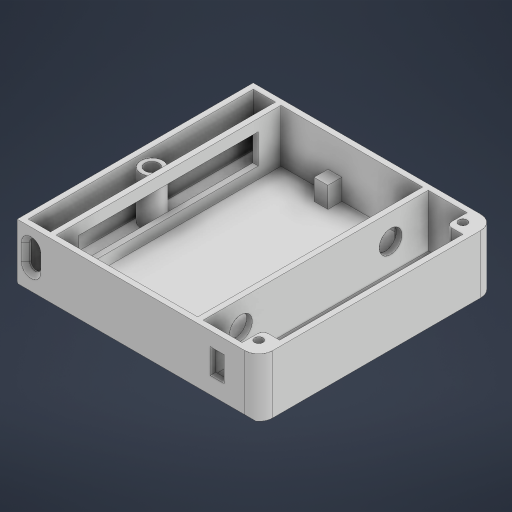
# Autodesk Inventor part: основа низ V2
Saved by Autodesk Inventor 2024 (Build 280153000, 153)
## iProperties
Created: 2026-05-29
Part Number: основа низ V2
Material: Типовые
Document SubType Name: Modeling
Designer: mitm
Density: 1 g/cm^3
Appearance: По умолчанию
Author: mitm
Autodesk Inventor part; units mm, degrees
ref_plane "YZ Plane" through (0, 0, 0) normal (1, 0, 0) x (0, 1, 0)
ref_plane "XZ Plane" through (0, 0, 0) normal (0, 1, 0) x (-1, 0, 0)
ref_plane "XY Plane" through (0, 0, 0) normal (0, 0, 1) x (1, 0, 0)
sketch "Эскиз1" plane through (0, 0, 0) normal (0, 1, 0) x (-1, 0, 0)
  line L0 (19.7795, 40.5) -> (-19.7795, 40.5)
  line L1 (-25.5, 34.7795) -> (-25.5, -34.7795)
  line L2 (-19.7795, -40.5) -> (19.7795, -40.5)
  line L3 (25.5, -34.7795) -> (25.5, 34.7795)
  line L4 (27.5, 42.5) -> (-27.5, 42.5)
  line L5 (-27.5, 42.5) -> (-27.5, -42.5)
  line L6 (-27.5, -42.5) -> (27.5, -42.5)
  line L7 (27.5, -42.5) -> (27.5, 42.5)
  line L8 (-27.5, 42.5) -> (-27.5, -42.5)
  line L9 (-27.5, -42.5) -> (-44.5, -42.5)
  line L10 (-49.5, -37.5) -> (-49.5, 37.5)
  line L11 (-44.5, 42.5) -> (-27.5, 42.5)
  line L12 (-27.5, 0) -> (-27.5, 33)
  line L13 (-27.5, 33) -> (-27.5, -33)
  line L14 (-47.5, -33) -> (-47.5, 33)
  line L15 (-27.5, 40.5) -> (-42.5, 40.5)
  line L16 (-47.5, 35.5) -> (-47.5, 33)
  line L17 (-27.5, -40.5) -> (-42.5, -40.5)
  line L18 (-47.5, -35.5) -> (-47.5, -33)
  circle A0 centre (-43.75, 36.75) radius 1.5
  circle A1 centre (-43.75, -36.75) radius 1.5
  arc A2 (-42.5, 40.5) -> (-47.5, 35.5) centre (-42.5, 35.5) ccw
  arc A3 (-44.5, 42.5) -> (-49.5, 37.5) centre (-44.5, 37.5) ccw
  arc A4 (-47.5, -35.5) -> (-42.5, -40.5) centre (-42.5, -35.5) ccw
  arc A5 (-49.5, -37.5) -> (-44.5, -42.5) centre (-44.5, -37.5) ccw
  line L19 (25.5, 40.5) -> (-25.5, 40.5)
  line L20 (-25.5, 40.5) -> (-25.5, -40.5)
  line L21 (-25.5, -40.5) -> (25.5, -40.5)
  line L22 (25.5, -40.5) -> (25.5, 40.5)
  line L23 (-27.5, 40.5) -> (-35, 40.5)
  line L24 (-27.5, 33) -> (-27.5, 40.5)
  line L25 (-47.5, 33) -> (-43.5, 33)
  line L26 (-37.5, 40.5) -> (-33.5, 40.5)
  line L27 (-37.5, 40.5) -> (-41.5, 40.5)
  line L28 (-41.5, 40.5) -> (-41.5, 35)
  arc A6 (-43.5, 33) -> (-41.5, 35) centre (-43.5, 35) ccw
  line L29 (-37.5, -40.5) -> (-33.5, -40.5)
  line L30 (-33.5, -40.5) -> (-41.5, -40.5)
  line L31 (-41.5, -40.5) -> (-41.5, -35)
  line L32 (-43.5, -33) -> (-47.5, -33)
  arc A7 (-41.5, -35) -> (-43.5, -33) centre (-43.5, -35) ccw
  line L33 (27.5, 42.5) -> (27.5, -42.5)
  line L34 (27.5, -42.5) -> (37.5, -42.5)
  line L35 (37.5, -42.5) -> (37.5, 42.5)
  line L36 (37.5, 42.5) -> (27.5, 42.5)
  line L37 (27.5, 40.5) -> (27.5, -40.5)
  line L38 (27.5, -40.5) -> (35.5, -40.5)
  line L39 (35.5, -40.5) -> (35.5, 40.5)
  line L40 (35.5, 40.5) -> (27.5, 40.5)
  line L41 (-25.5, -40.5) -> (-20.5, -40.5)
  line L42 (-20.5, -40.5) -> (-20.5, -35.5)
  line L43 (-20.5, -35.5) -> (-25.5, -35.5)
  line L44 (-25.5, -35.5) -> (-25.5, -40.5)
  line L45 (25.5, 40.5) -> (20.5, 40.5)
  line L46 (20.5, 40.5) -> (20.5, 35.5)
  line L47 (20.5, 35.5) -> (25.5, 35.5)
  line L48 (25.5, 35.5) -> (25.5, 40.5)
  line L49 (35.5, 40.5) -> (33.5, 40.5)
  line L50 (33.5, 40.5) -> (33.5, 20.5)
  line L51 (33.5, 20.5) -> (35.5, 20.5)
  line L52 (35.5, 20.5) -> (35.5, 40.5)
  line L53 (33.5, 40.5) -> (32.5, 40.5)
  line L54 (32.5, 40.5) -> (30.5, 40.5)
  line L55 (30.5, 40.5) -> (30.5, 20.5)
  line L56 (30.5, 20.5) -> (32.5, 20.5)
  line L57 (32.5, 20.5) -> (32.5, 40.5)
  line L58 (-3.7286, 40.5) -> (-8.7286, 40.5)
  line L59 (-8.7286, 40.5) -> (-8.7286, 35.5)
  line L60 (-8.7286, 35.5) -> (-3.7286, 35.5)
  line L61 (-3.7286, 35.5) -> (-3.7286, 40.5)
  line L62 (3.6011, -40.5) -> (8.6011, -40.5)
  line L63 (8.6011, -40.5) -> (8.6011, -35.5)
  line L64 (8.6011, -35.5) -> (3.6011, -35.5)
  line L65 (3.6011, -35.5) -> (3.6011, -40.5)
  point P0 (0, 0)
  point P1 (-49.5, -42.5)
  point P2 (-47.5, -40.5)
  point P3 (25.5, 37.3229)
  point P4 (22.3229, 40.5)
  point P5 (22.3229, -40.5)
  point P6 (25.5, -37.3229)
  point P7 (-41.5, -33)
  dimension "d112" = 5
  dimension "d113" = 5
  dimension "d114" = 5
  dimension "d115" = 5
  dimension "d116" = 2
  dimension "d117" = 20
  dimension "d118" = 1
  dimension "d119" = 2
  dimension "d120" = 5
  dimension "d121" = 5
  dimension "d122" = 5
  dimension "d123" = 5
  constraints: 132 end point, 26 point on line, 25 parallel, 18 perpendicular, 12 point on circle, 12 tangent, 9 horizontal, 8 centre point, 3 equal radius, 1 collinear, 1 midpoint, 1 vertical, 3 other
  measures "d112" distance of L43.end L42.end
  measures "d113" distance of L42.end L41.end
  measures "d114" distance of L47.end L46.end
  measures "d115" distance of L46.end L45.end
  measures "d116" distance of L51.end L50.end
  measures "d117" distance of L50.end L49.end
  measures "d118" distance of L49.end L53.end
  measures "d119" distance of L56.end L55.end
  measures "d120" distance of L60.end L59.end
  measures "d121" distance of L59.end L58.end
  measures "d122" distance of L64.end L63.end
  measures "d123" distance of L63.end L62.end
extrude "Выдавливание20" add sketch "Эскиз1" along normal blind 19 contours L7 L6 L5 L4 | L36 L35 L34 L7 L38 L39 L40 | L5 L15 A2 L16 L14 L18 A4 L17 L9 A5 L10 A3 L11 | L28 A6 L25 L16 A2 L15 | L17 A4 L18 L32 A7 L31
extrude "Выдавливание21" add sketch "Эскиз1" against normal blind 2 contours L19 L46 L47 L22 L3 L21 L2 L63 L64 L65 L42 L43 L20 L1 L0 L59 L60 L61 | L61 L60 L59 L0 | L19 L22 L47 L46 | L43 L42 L21 L20 | L2 L65 L64 L63 | L7 L6 L5 L4 | L36 L35 L34 L7 L38 L39 L40 | L5 L15 A2 L16 L14 L18 A4 L17 L9 A5 L10 A3 L11 | L40 L55 L56 L57 L50 L51 L39 L38 L7 | L5 L17 L31 A7 L32 L14 L25 A6 L28 L15 | L40 L57 L56 L55 | L51 L50 L40 L39 | L28 A6 L25 L16 A2 L15 | L17 A4 L18 L32 A7 L31 | A0 | A1
extrude "Выдавливание22" add sketch "Эскиз1" along normal blind 7.5 contours L61 L60 L59 L0 | L19 L22 L47 L46 | L43 L42 L21 L20 | L2 L65 L64 L63
sketch "Эскиз15" plane through (27.5, 19, 40.5) normal (1, 0, 0) x (0, 0, -1)
  line L0 (0, -19) -> (81, -19) projected
  line L1 (0, 0) -> (81, 0)
  line L2 (81, 0) -> (81, -19)
  line L3 (81, -19) -> (0, -19)
  line L4 (0, -19) -> (0, 0)
  line L5 (9.4545, -5.092) -> (71.5455, -5.092)
  line L6 (71.5455, -5.092) -> (71.5455, -13.908)
  line L7 (71.5455, -13.908) -> (9.4545, -13.908)
  line L8 (9.4545, -13.908) -> (9.4545, -5.092)
  line L9 (9.4545, -5.092) -> (71.5455, -13.908) construction
  line L10 (71.5455, -5.092) -> (9.4545, -13.908) construction
  circle A0 centre (13.5512, -9.1886) radius 4.0967
  circle A1 centre (67.4488, -9.1886) radius 4.0967
  point P0 (40.5, -19)
  point P1 (40.5, -9.5)
  constraints: 20 end point, 6 tangent, 4 parallel, 2 centre point, 2 horizontal, 2 midpoint, 2 perpendicular
extrude "Выдавливание23" cut sketch "Эскиз15" against normal blind 7.5 contours A0 | A1
sketch "Эскиз16" plane through (-25.5, 19, 40.5) normal (1, 0, 0) x (0, 0, -1)
  line L0 (0, -19) -> (0, 0) projected
  line L1 (81, -19) -> (0, -19) projected
  line L2 (0, 0) -> (81, 0)
  line L3 (81, 0) -> (81, -19)
  line L4 (81, -19) -> (0, -19)
  line L5 (0, -19) -> (0, 0)
  line L6 (0, 0) -> (81, 0) projected
  line L7 (5, -19) -> (81, -19) projected
  line L8 (0, 0) -> (81, -19)
  line L9 (81, 0) -> (0, 0) projected
  line L10 (81, 0) -> (0, -19)
  line L11 (8.1719, -4.1517) -> (72.8281, -4.1517)
  line L12 (72.8281, -4.1517) -> (72.8281, -14.8483)
  line L13 (72.8281, -14.8483) -> (8.1719, -14.8483)
  line L14 (8.1719, -14.8483) -> (8.1719, -4.1517)
  line L15 (8.1719, -4.1517) -> (72.8281, -14.8483) construction
  line L16 (72.8281, -4.1517) -> (8.1719, -14.8483) construction
  point P0 (40.5, -19)
  point P1 (40.5, -9.5)
  constraints: 24 end point, 4 parallel, 3 midpoint, 2 horizontal, 2 perpendicular
extrude "Выдавливание24" cut sketch "Эскиз16" against normal blind 7.5 contours L13 L14 L11 L8 L10 | L10 L8 L13 | L11 L10 L8 | L10 L11 L12 L13 L8
sketch "Эскиз17" plane through (-27.5, 19, 40.5) normal (0, 0, -1) x (-1, 0, 0)
  line L0 (8, 0) -> (0, 0)
  line L1 (0, 0) -> (0, -19)
  line L2 (0, -19) -> (8, -19)
  line L3 (8, -19) -> (8, 0)
  line L4 (8, 0) -> (7, 0)
  line L5 (7, 0) -> (7, -19)
  line L6 (0, -19) -> (0, 0) projected
  line L7 (0, 0) -> (7, -19)
  line L8 (7, 0) -> (0, -19)
  line L9 (3.5, -9.5) -> (7, -9.5)
  line L10 (7, -9.5) -> (7, -14.5)
  line L11 (7, -9.5) -> (7, -4.5)
  line L12 (7, -4.5) -> (3, -4.5)
  line L13 (3, -4.5) -> (3, -14.5)
  line L14 (3, -14.5) -> (7, -14.5)
  line L15 (7, -4.5) -> (3, -4.5)
  line L16 (3, -4.5) -> (3, -14.5)
  line L17 (3, -14.5) -> (7, -14.5)
  line L18 (7, -14.5) -> (7, -4.5)
  point P0 (-27.5, -19)
  dimension "d134" = 1
  dimension "d135" = 5
  dimension "d136" = 5
  dimension "d137" = 4
  constraints: 36 end point, 6 perpendicular, 4 parallel, 4 point on line, 2 horizontal, 2 midpoint
  measures "d134" distance of L0.start L4.end
  measures "d135" distance of L9.end L10.end
  measures "d136" distance of L9.end L11.end
  measures "d137" distance of L11.end L12.end
extrude "Выдавливание25" cut sketch "Эскиз17" against normal blind 7.5 contours L5 L9 L8 L12 | L8 L7 L13 L12 | L7 L8 L13 | L5 L14 L7 L9 | L7 L14 L13 L8
sketch "Эскиз18" plane through (41.5, 19, 40.5) normal (0, 0, -1) x (-1, 0, 0)
  line L0 (14, -19) -> (14, 0) projected
  line L1 (14, 0) -> (0, 0)
  line L2 (0, 0) -> (0, -19)
  line L3 (14, -19) -> (14, 0)
  line L4 (0, -19) -> (14, -19) projected
  line L5 (9.5, -5) -> (4.5, -5)
  line L6 (4.5, -5) -> (4.5, -14)
  line L7 (4.5, -14) -> (9.5, -14)
  line L8 (9.5, -14) -> (9.5, -5)
  line L9 (9.5, -5) -> (4.5, -14) construction
  line L10 (4.5, -5) -> (9.5, -14) construction
  point P0 (41.5, -19)
  point P1 (7, -9.5)
  dimension "d140" = 5
  dimension "d141" = 9
  constraints: 18 end point, 3 parallel, 2 horizontal, 2 midpoint, 2 perpendicular
  measures "d140" distance of L7.end L6.end
  measures "d141" distance of L6.end L5.end
extrude "Выдавливание26" cut sketch "Эскиз18" against normal blind 7.5 contours L8 L7 L6 L5
sketch "Эскиз19" plane through (0, -2, 0) normal (0, -1, 0) x (1, 0, 0)
  line L0 (49.5, -37.5) -> (49.5, 37.5) projected
  line L1 (49.5, 0) -> (48.5, 0)
  line L2 (48.5, 0) -> (48.5, 44.5812)
  line L3 (48.5, 0) -> (48.5, -47.6013)
  line L4 (46.5, -47.6013) -> (46.5, 43.7108)
  line L5 (44.5, 43.7108) -> (44.5, -47.6013)
  line L6 (44.5, -47.6013) -> (44.5, 43.7108)
  line L7 (42.5, 43.7108) -> (42.5, -47.6013)
  line L8 (46.5, 0) -> (46.5, -47.6013)
  line L9 (42.5, -47.6013) -> (42.5, 43.7108)
  line L10 (40.5, 43.7108) -> (40.5, -47.6013)
  line L11 (44.5, 0) -> (44.5, -47.6013)
  line L12 (40.5, -47.6013) -> (40.5, 43.7108)
  line L13 (38.5, 43.7108) -> (38.5, -47.6013)
  line L14 (42.5, 0) -> (42.5, -47.6013)
  line L15 (38.5, -47.6013) -> (38.5, 43.7108)
  line L16 (36.5, 43.7108) -> (36.5, -47.6013)
  line L17 (40.5, 0) -> (40.5, -47.6013)
  line L18 (36.5, -47.6013) -> (36.5, 43.7108)
  line L19 (34.5, 43.7108) -> (34.5, -47.6013)
  line L20 (38.5, 0) -> (38.5, -47.6013)
  line L21 (34.5, -47.6013) -> (34.5, 43.7108)
  line L22 (32.5, 43.7108) -> (32.5, -47.6013)
  line L23 (36.5, 0) -> (36.5, -47.6013)
  line L24 (32.5, -47.6013) -> (32.5, 43.7108)
  line L25 (30.5, 43.7108) -> (30.5, -47.6013)
  line L26 (34.5, 0) -> (34.5, -47.6013)
  line L27 (30.5, -47.6013) -> (30.5, 43.7108)
  line L28 (28.5, 43.7108) -> (28.5, -47.6013)
  line L29 (32.5, 0) -> (32.5, -47.6013)
  line L30 (28.5, -47.6013) -> (28.5, 43.7108)
  line L31 (26.5, 43.7108) -> (26.5, -47.6013)
  line L32 (30.5, 0) -> (30.5, -47.6013)
  line L33 (26.5, -47.6013) -> (26.5, 43.7108)
  line L34 (24.5, 43.7108) -> (24.5, -47.6013)
  line L35 (28.5, 0) -> (28.5, -47.6013)
  line L36 (24.5, -47.6013) -> (24.5, 43.7108)
  line L37 (22.5, 43.7108) -> (22.5, -47.6013)
  line L38 (26.5, 0) -> (26.5, -47.6013)
  line L39 (22.5, -47.6013) -> (22.5, 43.7108)
  line L40 (20.5, 43.7108) -> (20.5, -47.6013)
  line L41 (24.5, 0) -> (24.5, -47.6013)
  line L42 (20.5, -47.6013) -> (20.5, 43.7108)
  line L43 (18.5, 43.7108) -> (18.5, -47.6013)
  line L44 (22.5, 0) -> (22.5, -47.6013)
  line L45 (18.5, -47.6013) -> (18.5, 43.7108)
  line L46 (16.5, 43.7108) -> (16.5, -47.6013)
  line L47 (20.5, 0) -> (20.5, -47.6013)
  line L48 (16.5, -47.6013) -> (16.5, 43.7108)
  line L49 (14.5, 43.7108) -> (14.5, -47.6013)
  line L50 (18.5, 0) -> (18.5, -47.6013)
  line L51 (14.5, -47.6013) -> (14.5, 43.7108)
  line L52 (12.5, 43.7108) -> (12.5, -47.6013)
  line L53 (16.5, 0) -> (16.5, -47.6013)
  line L54 (12.5, -47.6013) -> (12.5, 43.7108)
  line L55 (10.5, 43.7108) -> (10.5, -47.6013)
  line L56 (14.5, 0) -> (14.5, -47.6013)
  line L57 (10.5, -47.6013) -> (10.5, 43.7108)
  line L58 (8.5, 43.7108) -> (8.5, -47.6013)
  line L59 (12.5, 0) -> (12.5, -47.6013)
  line L60 (8.5, -47.6013) -> (8.5, 43.7108)
  line L61 (6.5, 43.7108) -> (6.5, -47.6013)
  line L62 (10.5, 0) -> (10.5, -47.6013)
  arc A0 (44.5, -42.5) -> (49.5, -37.5) centre (44.5, -37.5) ccw projected
  line L63 (44.5, -42.5) -> (6.5, -42.5)
  line L64 (-37.5, -42.5) -> (44.5, -42.5) projected
  arc A1 (49.5, 37.5) -> (44.5, 42.5) centre (44.5, 37.5) ccw projected
  line L65 (44.5, 42.5) -> (6.5, 42.5)
  point P0 (0, 0)
  point P1 (8.5, 42.5)
  point P2 (8.5, -42.5)
  point P3 (12.5, 42.5)
  point P4 (10.5, 42.5)
  point P5 (10.5, -42.5)
  point P6 (12.5, -42.5)
  point P7 (16.5, 42.5)
  point P8 (14.5, 42.5)
  point P9 (14.5, -42.5)
  point P10 (16.5, -42.5)
  point P11 (20.5, 42.5)
  point P12 (18.5, 42.5)
  point P13 (18.5, -42.5)
  point P14 (20.5, -42.5)
  point P15 (24.5, 42.5)
  point P16 (22.5, 42.5)
  point P17 (22.5, -42.5)
  point P18 (24.5, -42.5)
  point P19 (28.5, 42.5)
  point P20 (26.5, 42.5)
  point P21 (26.5, -42.5)
  point P22 (28.5, -42.5)
  point P23 (32.5, 42.5)
  point P24 (30.5, 42.5)
  point P25 (30.5, -42.5)
  point P26 (32.5, -42.5)
  point P27 (36.5, 42.5)
  point P28 (34.5, 42.5)
  point P29 (34.5, -42.5)
  point P30 (36.5, -42.5)
  point P31 (40.5, 42.5)
  point P32 (38.5, 42.5)
  point P33 (38.5, -42.5)
  point P34 (40.5, -42.5)
  point P35 (42.5, 42.5)
  point P36 (42.5, -42.5)
  dimension "d144" = 1
  dimension "d145" = 2
  dimension "d146" = 2
  dimension "d149" = 2
  constraints: 124 end point, 3 point on line, 2 horizontal, 2 vertical, 1 midpoint, 1 perpendicular, 178 other
  measures "d144" distance of L1.start L1.end
  measures "d145" distance of L3.end L4.start
  measures "d146" distance of L4.end L5.start
  measures "d149" distance of L4.start L6.start
extrude "Выдавливание27" add sketch "Эскиз19" along normal blind 1 contours L63 L7 L65 L5 | L63 L13 L65 L10 | L63 L19 L65 L16 | L63 L25 L65 L22 | L63 L31 L65 L28 | L63 L37 L65 L34 | L63 L43 L65 L40 | L63 L49 L65 L46 | L63 L55 L65 L52 | L63 L61 L65 L58
chamfer "Фаска5" distance 2 angle 45 2 edges at (7.5, -3, 42.5) (7.5, -3, -42.5)
fillet "Сопряжение1" radius 2 1 edges at (-37.5, -2, 0)
sketch "Эскиз20" plane through (0, 0, 0) normal (0, 1, 0) x (1, 0, 0)
  line L0 (-27.5, -40.5) -> (-35.5, -40.5) projected
  line L1 (-27.5, 40.4805) -> (-27.5, -40.5)
  line L2 (-35.5, 41.5) -> (-35.5, -41.5) projected
  line L3 (-27.5, -40.5) -> (-35.5, -40.5)
  line L4 (-35.5, -40.5) -> (-35.5, 40.5)
  line L5 (-35.5, 40.5) -> (-27.5, 40.5)
  line L6 (-27.5, 40.5) -> (-27.5, -40.5)
  line L7 (-35.5, -40.5) -> (-27.5, 40.5)
  line L8 (-35.5, 40.5) -> (-27.5, -40.5)
  circle A0 centre (-31.5, 0) radius 4
  circle A1 centre (-31.5, 0) radius 2.5
  point P0 (0, 0)
  dimension "d161" = 81
  dimension "d163" = 5
  constraints: 14 end point, 2 centre point, 2 parallel, 1 coincident, 1 horizontal, 1 midpoint, 1 perpendicular, 1 point on line
  measures "d161" distance of L3.end L4.end
  measures "d163" diameter of A1
extrude "Выдавливание28" add sketch "Эскиз20" along normal blind 17 contours A0 L8 A1 L7 | A0 L7 A1 L8 | A0 L8 A1 L7 | L7 A1 L8 A0
fillet "Сопряжение2" radius 2 4 edges at (-34.5, 4.5, 41.5) (-30.5, 4.5, 41.5) (-34.5, 14.5, 41.5) (-30.5, 14.5, 41.5)
chamfer "Фаска6" distance 1.5 angle 45 8 edges at (-34.5, 9.5, 42.5) (-32.5, 14.5, 42.5) (-33.9142, 13.9142, 42.5) (-31.0858, 13.9142, 42.5) (-30.5, 9.5, 42.5) (-33.9142, 5.0858, 42.5) (-31.0858, 5.0858, 42.5) (-32.5, 4.5, 42.5)
